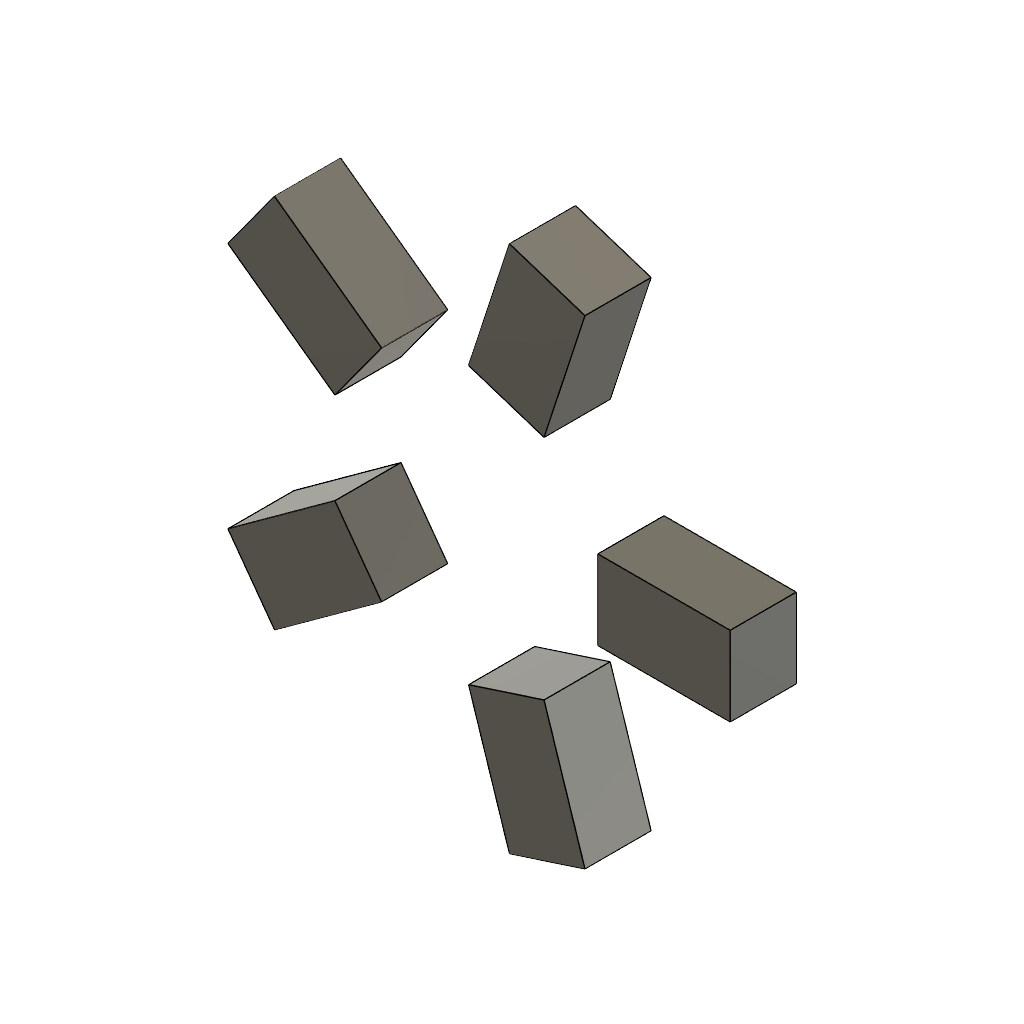
pat_circ_bodies (Autodesk Fusion 360 design; units mm, degrees)
part number: 2026-11-13-14-44-08-851
Autodesk Fusion 360 part; units mm, degrees
sketch "Sketch1" plane through (0, 0, 0) normal (0, 0, 1) x (1, 0, 0)
  line L0 (10, -3) -> (20, -3)
  line L1 (20, -3) -> (20, 3)
  line L2 (20, 3) -> (10, 3)
  line L3 (10, 3) -> (10, -3)
extrude "Extrude1" add sketch "Sketch1" along normal blind 5 makes body 1
pattern_circular "C-Pattern1" count 5 over 360 about axis through (0, 0, 1.75) along (0, 0, 1) of bodies 1 makes body 2 at (3.1692, 12.9898, 0) makes body 3 at (-14.0714, 8.9874, 0) makes body 4 at (-11.3747, -7.0281, 0) makes body 5 at (4.1992, -16.16, 0)
